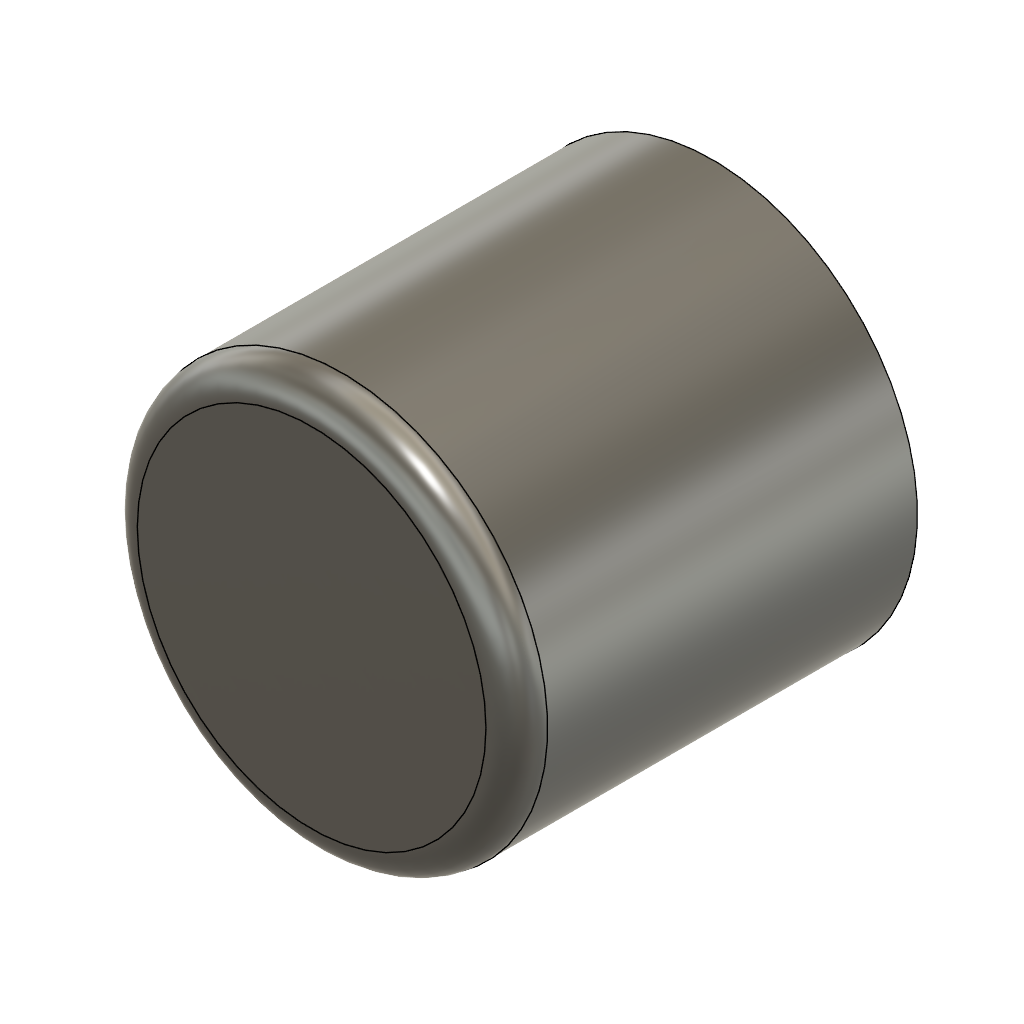
Reconstructed (Autodesk Fusion 360 design; units mm, degrees)
part number: 2026-11-25-22-55-25-310
Autodesk Fusion 360 part; units mm, degrees
sketch "Disc sketch" plane through (0, 0, 0) normal (0, 0, 1) x (1, 0, 0)
  circle A0 centre (0, 0) radius 19.3
extrude "Disc extrude" add sketch "Disc sketch" along normal blind 37.7
fillet "Rim round" radius 2.9 1 edges at (-17.9939, -6.9792, 37.7)
